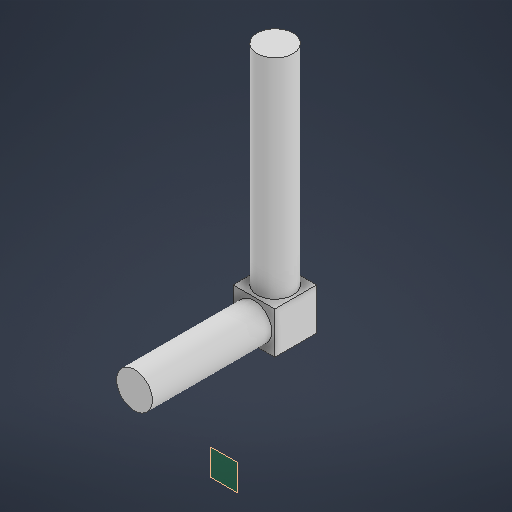
# Autodesk Inventor part: Handles for rear open
Saved by Autodesk Inventor 2026 (Build 300175050, 175E)
## iProperties
Created: 2026-07-16
Part Number: Handles for rear open
Material: handle
Document SubType Name: Modeling
Designer: Anura
Mass: 1202.13 g
Surface Area: 1932.7 cm^2
Volume: 3005.51 cm^3
Density: 0.399975 g/cm^3
Appearance: Generic
Author: Anura
Autodesk Inventor part; units mm, degrees
ref_plane "YZ Plane" through (0, 0, 0) normal (1, 0, 0) x (0, 1, 0)
ref_plane "XZ Plane" through (0, 0, 0) normal (0, 1, 0) x (-1, 0, 0)
ref_plane "XY Plane" through (0, 0, 0) normal (0, 0, 1) x (1, 0, 0)
ref_plane "Work Plane2" through (0, 0, -250) normal (0, 0, -1) x (-1, 0, 0)
sketch "Sketch3" plane through (0, 0, -250) normal (0, 0, -1) x (-1, 0, 0)
  circle A0 centre (75, 20.3765) radius 15
  point P0 (0, 0)
  dimension "d10" = 30
  constraints: 1 centre point
  measures "d10" diameter of A0
extrude "Extrusion3" add sketch "Sketch3" along normal blind 100
sketch "Sketch4" plane through (-75, 20.3765, -350) normal (0, 0, -1) x (-1, 0, 0)
  line L0 (-17.5, -17.5) -> (17.5, -17.5)
  line L1 (17.5, -17.5) -> (17.5, 17.5)
  line L2 (17.5, 17.5) -> (-17.5, 17.5)
  line L3 (-17.5, 17.5) -> (-17.5, -17.5)
  line L4 (-17.5, -17.5) -> (17.5, 17.5) construction
  line L5 (17.5, -17.5) -> (-17.5, 17.5) construction
  point P0 (-75, -20.3765)
  point P1 (0, 0)
  dimension "d13" = 35
  dimension "d14" = 35
  constraints: 12 end point, 2 midpoint, 2 parallel, 1 horizontal, 1 perpendicular
  measures "d13" distance of L2.end L1.end
  measures "d14" distance of L1.end L0.end
extrude "Extrusion4" add sketch "Sketch4" along normal blind 35
sketch "Sketch5" plane through (-92.5, 37.8765, -350) normal (0, 1, 0) x (1, 0, 0)
  circle A0 centre (17.5, 17.7547) radius 15
  point P0 (92.5, -350)
  dimension "d17" = 30
  constraints: 1 centre point
  measures "d17" diameter of A0
extrude "Extrusion5" add sketch "Sketch5" along normal blind 175
body "Solid1"
